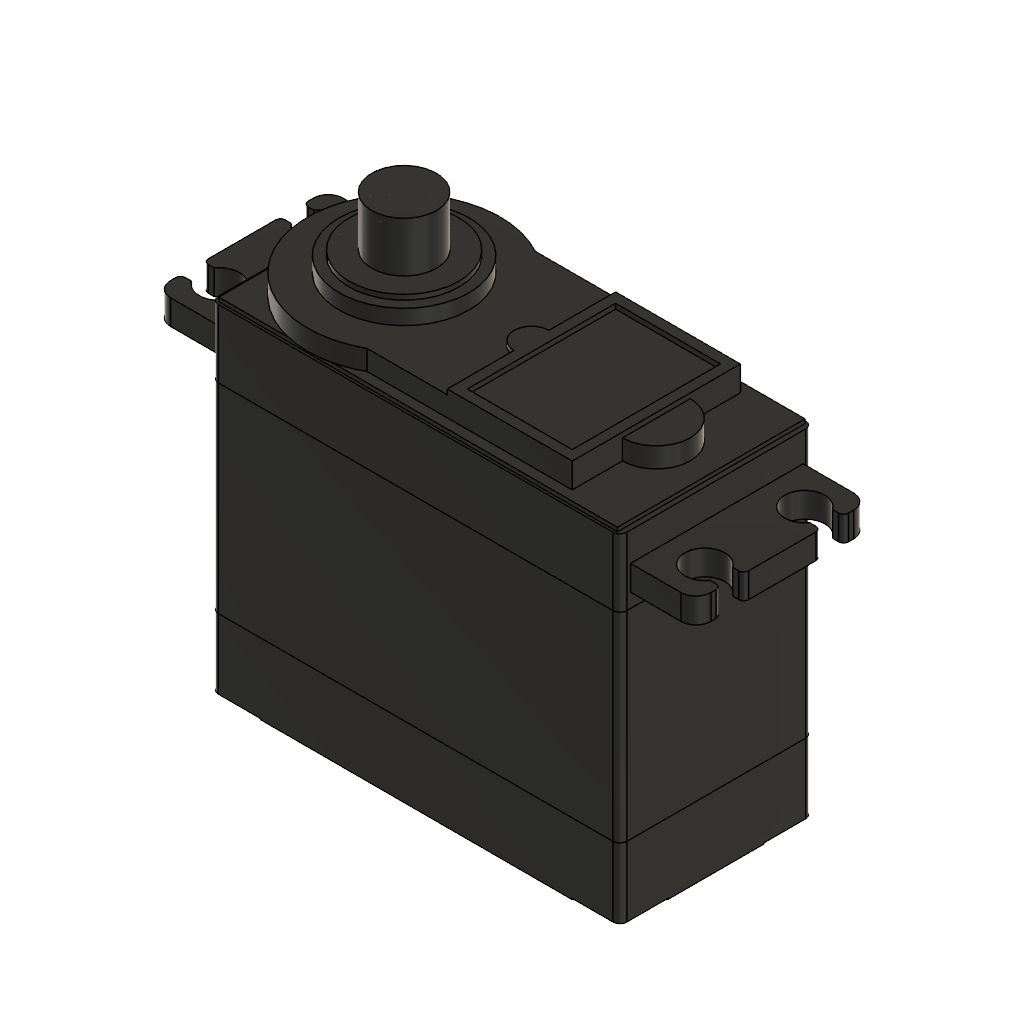
Small_arm_assembly (Autodesk Fusion 360 archive; units mm, degrees)
design "small_arm_servo_black"
part number: 2026-10-12-23-47-02-979
Autodesk Fusion 360 part; units mm, degrees
sketch "Sketch1" plane through (0, 0, 0) normal (0, 1, 0) x (1, 0, 0)
  line L0 (20.45, -10) -> (-20.45, -10)
  line L1 (-20.45, -10) -> (-20.45, 10)
  line L2 (-20.45, 10) -> (20.45, 10)
  line L3 (20.45, 10) -> (20.45, -10)
  line L4 (20.45, -10) -> (-20.45, 10) construction
  line L5 (-20.45, -10) -> (20.45, 10) construction
  dimension "d1" = 20
  dimension "d2" = 40.9
  constraint horizontal L0
  constraint perpendicular L0 L1
  constraint parallel L0 L2
  constraint parallel L1 L3
  constraint coincident L4 origin
  constraint coincident L5 origin
  measures "d1" distance of L0.start L2.end
  measures "d2" distance of L1.end L2.end
extrude "Extrude1" add sketch "Sketch1" along normal blind 19.3 contours L0 L1 L2 L3 picked at (-6.816667, -3.333333) makes body 1
sketch "Sketch2" plane through (0, 0, 10) normal (0, 0, 1) x (-1, 0, 0)
  line L0 (20.45, 0) -> (-20.45, 0)
  line L1 (-20.45, 0) -> (-20.45, -19.3)
  line L2 (-20.45, -19.3) -> (20.45, -19.3)
  line L3 (20.45, -19.3) -> (20.45, 0)
  line L4 (20.45, 0) -> (-20.45, 0)
  line L5 (-20.45, 0) -> (-20.45, -19.3)
  line L6 (-20.45, -19.3) -> (20.45, -19.3)
  line L7 (20.45, -19.3) -> (20.45, 0)
  dimension "d5" = 0
  measures "d5" distance of L2
extrude "Extrude2" add sketch "Sketch2" along normal blind 6.8 separate body contours L0 L1 L2 L3 L4 L5 L6 L7 picked at (-6.816667, -6.433333) makes body 2
sketch "Sketch3" plane through (0, 0, -10) normal (0, 0, -1) x (1, 0, 0)
  line L0 (20.45, 0) -> (-20.45, 0)
  line L1 (-20.45, 0) -> (-20.45, -19.3)
  line L2 (-20.45, -19.3) -> (20.45, -19.3)
  line L3 (20.45, -19.3) -> (20.45, 0)
  line L4 (-20.45, -19.3) -> (20.45, -19.3)
  line L5 (20.45, -19.3) -> (20.45, 0)
  line L6 (20.45, 0) -> (-20.45, 0)
  line L7 (-20.45, 0) -> (-20.45, -19.3)
  dimension "d8" = 0
  measures "d8" distance of L0
extrude "Extrude3" add sketch "Sketch3" along normal blind 8.5 separate body contours L0 L1 L2 L3 L4 L5 L6 L7 picked at (-6.816667, -6.433333) makes body 3
chamfer "Chamfer1" distance 2 angle 35 1 faces at (-6.816667, 6.433333, -18.5) tangent chain off on bodies 3
sketch "Sketch4" plane through (0, 0, -18.5) normal (0, 0, -1) x (1, 0, 0)
  line L0 (18.45, -17.3) -> (18.45, -2)
  line L1 (18.45, -2) -> (-18.45, -2)
  line L2 (-18.45, -2) -> (-18.45, -17.3)
  line L3 (-18.45, -17.3) -> (18.45, -17.3)
  line L4 (-20.450001, 0) -> (-15.570001, 0)
  line L5 (-15.570001, 0) -> (-15.570001, -2.88)
  line L6 (-17.570001, -4.88) -> (-20.450001, -4.88)
  line L7 (-20.450001, -4.88) -> (-20.450001, 0)
  arc A0 (-17.570001, -4.88) -> (-15.570001, -2.88) centre (-17.570001, -2.88) ccw
  line L8 (0, 0) -> (0, -19.328376) construction
  line L9 (20.450001, 0) -> (15.570001, 0)
  line L10 (20.450001, -4.88) -> (20.450001, 0)
  line L11 (17.570001, -4.88) -> (20.450001, -4.88)
  line L12 (15.570001, 0) -> (15.570001, -2.88)
  arc A1 (15.570001, -2.88) -> (17.570001, -4.88) centre (17.570001, -2.88) ccw
  line L13 (18.45, -9.65) -> (0, -9.664188) construction
  line L14 (-20.435113, -19.359816) -> (-15.555119, -19.352311)
  line L15 (-20.442619, -14.479822) -> (-20.435113, -19.359816)
  line L16 (-17.562622, -14.475392) -> (-20.442619, -14.479822)
  line L17 (-15.555119, -19.352311) -> (-15.559549, -16.472314)
  arc A2 (-15.559549, -16.472314) -> (-17.562622, -14.475392) centre (-17.559546, -16.47539) ccw
  line L18 (20.46484, -19.296913) -> (15.584846, -19.304418)
  line L19 (15.584846, -19.304418) -> (15.580416, -16.424421)
  arc A3 (17.577338, -14.421348) -> (15.580416, -16.424421) centre (17.580414, -16.421345) ccw
  line L20 (17.577338, -14.421348) -> (20.457335, -14.416918)
  line L21 (20.457335, -14.416918) -> (20.46484, -19.296913)
  dimension "d13" = 4.88
  dimension "d14" = 4.88
  dimension "d15" = 2
  constraint horizontal L4
  constraint vertical L5
  constraint horizontal L6
  constraint vertical L7
  constraint tangent L5 A0
  constraint tangent L6 A0
  constraint coincident L8.start origin
  constraint vertical L8
  constraint symmetric A0 L8 A1
  constraint midpoint L0 L13.start
  constraint symmetric A0 L13 A2
  constraint symmetric A1 L13 A3
  measures "d15" radius of A0
extrude "Extrude4" cut sketch "Sketch4" against normal blind 1.5 contours L0 L3 L19 A3 L20 | L0 L3 L18 L19 L20 L21 | L0 L1 L11 L12 A1 | L0 L1 L9 L10 L11 L12 | L2 L3 L14 L15 L16 L17 | L2 L3 L16 L17 A2 | L1 L2 L5 L6 A0 | L1 L2 L4 L5 L6 L7 picked at (16.537393, -17.00814) picked at (19.790725, -17.00461) picked at (16.530001, -2.293333) picked at (19.783334, -2.293333) picked at (-18.146744, -18.670709) picked at (-18.154207, -15.417383) picked at (-16.530001, -2.293333) picked at (-19.783334, -2.293333) bodies 3
sketch "Sketch5" plane through (0, 0, 16.8) normal (0, 0, 1) x (-1, 0, 0)
  line L0 (20.45, -19.3) -> (20.45, 0)
  line L1 (20.45, 0) -> (-20.45, 0)
  line L2 (-20.45, 0) -> (-20.45, -19.3)
  line L3 (-20.45, -19.3) -> (20.45, -19.3)
  line L4 (0, -19.3) -> (0, 0)
  line L5 (-19.95, -19.05) -> (19.95, -19.05)
  line L6 (19.95, -19.05) -> (19.95, -0.25)
  line L7 (19.95, -0.25) -> (-19.95, -0.25)
  line L8 (-19.95, -0.25) -> (-19.95, -19.05)
  line L9 (-19.95, -19.05) -> (19.95, -0.25) construction
  line L10 (19.95, -19.05) -> (-19.95, -0.25) construction
  point P0 (0, -9.65)
  dimension "d18" = 0.25
  dimension "d19" = 0.5
  constraint midpoint L3 L4.start
  constraint coincident L4.end origin
  constraint horizontal L5
  constraint perpendicular L5 L6
  constraint parallel L5 L7
  constraint parallel L6 L8
  constraint coincident L9 P0
  constraint coincident L10 P0
  constraint midpoint L4 P0
  measures "d18" distance of L3 L5
  measures "d19" distance of L2 L8
extrude "Extrude5" add sketch "Sketch5" along normal blind 0.4 contours L4 L5 L7 L8 | L4 L5 L6 L7 picked at (-13.3, -12.783333) picked at (13.3, -12.783333) bodies 2
sketch "Sketch6" plane through (0, 0, 17.2) normal (0, 0, 1) x (-1, 0, 0)
  line L0 (-19.95, -0.25) -> (-19.95, -19.05)
  line L1 (-19.95, -19.05) -> (19.95, -19.05)
  line L2 (19.95, -19.05) -> (19.95, -0.25)
  line L3 (19.95, -0.25) -> (-19.95, -0.25)
  line L4 (19.95, -9.65) -> (-20.844849, -9.65)
  line L5 (-20.45, -19.3) -> (20.45, -19.3)
  line L6 (20.45, -19.3) -> (20.45, 0)
  line L7 (6.09, -20) -> (6.09, 5)
  arc A0 (6.09, -18.072494) -> (6.09, -1.227506) centre (10.8, -9.65) ccw
  line L8 (6.09, -18.072494) -> (-14.45, -18.072494)
  line L9 (-20.45, 0) -> (-20.45, -19.3)
  line L10 (-14.45, -18.072494) -> (-14.45, -13.044849)
  arc A1 (-17.844849, -9.65) -> (-14.45, -13.044849) centre (-14.45, -9.65) ccw
  line L11 (6.09, -1.227506) -> (-14.45, -1.227506)
  line L12 (-14.45, -1.227506) -> (-14.45, -6.255151)
  arc A2 (-14.45, -6.255151) -> (-17.844849, -9.65) centre (-14.45, -9.65) ccw
  dimension "d22" = 14.36
  dimension "d25" = 6
  dimension "d26" = 3
  constraint midpoint L2 L4.start
  constraint perpendicular L0 L4
  constraint coincident L4 A0.centre
  constraint tangent L5 A0
  constraint tangent L6 A0
  constraint perpendicular L1 L7
  constraint horizontal L8
  constraint coincident L4 A1.centre
  constraint perpendicular L10 A1
  constraint symmetric L4 A1 A2
  measures "d22" distance of L6 L7.end
extrude "Extrude6" add sketch "Sketch6" along normal blind 2 contours L4 L7 L11 L12 A2 | L4 L7 L8 L10 A1 | L3 A0 | L2 L3 L4 L7 A0 | L1 L2 L4 L7 A0 | L1 A0 | L2 A0 picked at (-0.756667, -5.710886) picked at (-0.756667, -13.589114) picked at (10.8, -0.166667) picked at (14.908099, -7.795265) picked at (14.908099, -11.504735) picked at (11.287307, -19.096207) picked at (20.264671, -9.304002) bodies 2
sketch "Sketch7" plane through (0, 0, 19.2) normal (0, 0, 1) x (-1, 0, 0)
  arc A0 (6.09, -18.072494) -> (6.09, -1.227506) centre (10.8, -9.65) ccw
  line L0 (6.09, -1.227506) -> (-14.45, -1.227506)
  line L1 (-14.45, -1.227506) -> (-14.45, -6.255151)
  arc A1 (-14.45, -6.255151) -> (-14.45, -13.044849) centre (-14.45, -9.65) ccw
  line L2 (-14.45, -13.044849) -> (-14.45, -18.072494)
  line L3 (-14.45, -18.072494) -> (6.09, -18.072494)
  circle A2 centre (10.8, -9.65) radius 6.5
  dimension "d29" = 13
  constraint concentric A0 A2
  measures "d29" diameter of A2
extrude "Extrude7" add sketch "Sketch7" along normal blind 1.5 contours A2 picked at (9.021353, -11.740864) bodies 2
sketch "Sketch8" plane through (0, 0, 20.7) normal (0, 0, 1) x (-1, 0, 0)
  circle A0 centre (10.8, -9.65) radius 6.5
  circle A1 centre (10.8, -9.65) radius 5.5
  dimension "d32" = 11
  constraint concentric A0 A1
  measures "d32" diameter of A1
extrude "Extrude8" add sketch "Sketch8" along normal blind 0.5 contours A1 picked at (14.20366, -10.985838) bodies 2
sketch "Sketch9" plane through (0, 0, 21.2) normal (0, 0, 1) x (-1, 0, 0)
  circle A0 centre (10.8, -9.65) radius 5.5
  circle A1 centre (10.8, -9.65) radius 3.25
  dimension "d35" = 6.5
  constraint concentric A0 A1
  measures "d35" diameter of A1
extrude "Extrude9" add sketch "Sketch9" along normal blind 5 contours A1 picked at (11.651589, -11.26871) bodies 2
sketch "Sketch10" plane through (0, 0, 19.2) normal (0, 0, 1) x (-1, 0, 0)
  circle A0 centre (10.8, -9.65) radius 6.5
  arc A1 (6.09, -18.072494) -> (6.09, -1.227506) centre (10.8, -9.65) ccw
  line L0 (6.09, -1.227506) -> (-14.45, -1.227506)
  line L1 (-14.45, -1.227506) -> (-14.45, -6.255151)
  arc A2 (-14.45, -6.255151) -> (-14.45, -13.044849) centre (-14.45, -9.65) ccw
  line L2 (-14.45, -13.044849) -> (-14.45, -18.072494)
  line L3 (-14.45, -18.072494) -> (6.09, -18.072494)
  line L4 (-14.45, -18.072494) -> (-1.95, -18.072494)
  line L5 (-1.95, -1.227506) -> (-14.45, -1.227506)
  line L6 (-14.45, -1.227506) -> (-14.45, -18.072494)
  line L7 (-13.45, -17.072494) -> (-2.95, -17.072494)
  line L8 (-2.95, -17.072494) -> (-2.95, -2.227506)
  line L9 (-2.95, -2.227506) -> (-13.45, -2.227506)
  line L10 (-13.45, -2.227506) -> (-13.45, -17.072494)
  arc A3 (-1.95, -11.4) -> (-1.95, -7.9) centre (-1.95, -9.65) ccw
  line L11 (-1.95, -18.072494) -> (-1.95, -11.4)
  line L12 (-1.95, -7.9) -> (-1.95, -1.227506)
  dimension "d38" = 12.5
  dimension "d40" = 3.5
  dimension "d41" = 1
  dimension "d42" = 1
  dimension "d43" = 1
  dimension "d44" = 1
  constraint horizontal L4
  constraint vertical L11
  constraint horizontal L5
  constraint vertical L6
  constraint collinear L11 L12
  constraint coincident A3.centre L11
  measures "d40" diameter of A3
  measures "d41" distance of L4 L7
  measures "d42" distance of L8 L11
  measures "d43" distance of L5 L9
  measures "d44" distance of L6 L10
extrude "Extrude10" add sketch "Sketch10" along normal blind 0.5 contours L0 L1 L2 L3 L4 L5 L6 A3 L11 L12 picked at (-13.783333, -8.518384) bodies 2
fillet "Fillet1" radius 0.7 4 edges at (20.45, 0, 0) (20.45, 19.3, 0) (-20.45, 0, 0) (-20.45, 19.3, 0) on bodies 1
fillet "Fillet2" radius 0.7 4 edges at (-20.45, 19.3, 13.4) (-20.45, 0, 13.4) (20.45, 0, 13.4) (20.45, 19.3, 13.4) on bodies 2
fillet "Fillet3" radius 0.7 4 edges at (20.45, 0, -13.5) (20.45, 19.3, -13.549792) (-20.45, 0, -13.5) (-20.45, 19.3, -13.549792) on bodies 3
sketch "Sketch11" plane through (0, 0, 17.2) normal (0, 0, 1) x (-1, 0, 0)
  arc A0 (6.09, -18.072494) -> (8.617685, -19.05) centre (10.8, -9.65) ccw
  line L0 (6.09, -18.072494) -> (-14.45, -18.072494)
  line L1 (-14.45, -18.072494) -> (-14.45, -13.044849)
  arc A1 (-14.45, -6.255151) -> (-14.45, -13.044849) centre (-14.45, -9.65) ccw
  line L2 (-14.45, -6.255151) -> (-14.45, -1.227506)
  line L3 (-14.45, -1.227506) -> (6.09, -1.227506)
  arc A2 (8.617685, -0.25) -> (6.09, -1.227506) centre (10.8, -9.65) ccw
  line L4 (8.617685, -0.25) -> (-19.95, -0.25)
  line L5 (-19.95, -0.25) -> (-19.95, -19.05)
  line L6 (-19.95, -19.05) -> (8.617685, -19.05)
  line L7 (-20.5, -18.3) -> (-25.55, -18.3)
  line L8 (-0.197497, -9.659083) -> (-48.000001, -9.659083)
  line L9 (-19.75, -19.3) -> (19.75, -19.3)
  line L10 (0, -19.3) -> (0, 0)
  line L11 (-25.95, -18.3) -> (-25.95, -9.659083)
  arc A3 (-25.95, -15.789348) -> (-25.95, -13.528818) centre (-24.3, -14.659083) ccw
  line L12 (-25.95, -15.789348) -> (-26.55, -15.789348)
  line L13 (-25.95, -13.528818) -> (-26.55, -13.528818)
  line L14 (-27.05, -16.8) -> (-27.05, -16.289348)
  line L15 (-27.05, -13.028818) -> (-27.05, -9.659083)
  arc A4 (-26.55, -15.789348) -> (-27.05, -16.289348) centre (-26.55, -16.289348) ccw
  arc A5 (-27.05, -13.028818) -> (-26.55, -13.528818) centre (-26.55, -13.028818) ccw
  arc A6 (-27.05, -16.8) -> (-25.55, -18.3) centre (-25.55, -16.8) ccw
  line L16 (-25.95, -3.528818) -> (-26.55, -3.528818)
  line L17 (-27.05, -2.518166) -> (-27.05, -3.028818)
  arc A7 (-25.95, -5.789348) -> (-25.95, -3.528818) centre (-24.3, -4.659083) ccw
  arc A8 (-25.55, -1.018166) -> (-27.05, -2.518166) centre (-25.55, -2.518166) ccw
  arc A9 (-27.05, -3.028818) -> (-26.55, -3.528818) centre (-26.55, -3.028818) ccw
  arc A10 (-26.55, -5.789348) -> (-27.05, -6.289348) centre (-26.55, -6.289348) ccw
  line L18 (-20.5, -1.018166) -> (-25.55, -1.018166)
  line L19 (-25.95, -5.789348) -> (-26.55, -5.789348)
  line L20 (-27.05, -6.289348) -> (-27.05, -9.659083)
  line L21 (-20.5, -18.3) -> (-20.5, -1.018166)
  line L22 (25.95, -15.789348) -> (26.55, -15.789348)
  line L23 (25.95, -18.3) -> (25.95, -9.659083)
  line L24 (27.05, -13.028818) -> (27.05, -9.659083)
  line L25 (20.5, -18.3) -> (25.55, -18.3)
  line L26 (25.95, -3.528818) -> (26.55, -3.528818)
  arc A11 (27.05, -16.289348) -> (26.55, -15.789348) centre (26.55, -16.289348) ccw
  arc A12 (27.05, -6.289348) -> (26.55, -5.789348) centre (26.55, -6.289348) ccw
  line L27 (20.5, -18.3) -> (20.5, -1.018166)
  arc A13 (27.05, -2.518166) -> (25.55, -1.018166) centre (25.55, -2.518166) ccw
  arc A14 (25.95, -3.528818) -> (25.95, -5.789348) centre (24.3, -4.659083) ccw
  line L28 (25.95, -5.789348) -> (26.55, -5.789348)
  arc A15 (25.95, -13.528818) -> (25.95, -15.789348) centre (24.3, -14.659083) ccw
  line L29 (27.05, -6.289348) -> (27.05, -9.659083)
  arc A16 (26.55, -3.528818) -> (27.05, -3.028818) centre (26.55, -3.028818) ccw
  line L30 (27.05, -16.8) -> (27.05, -16.289348)
  line L31 (20.5, -1.018166) -> (25.55, -1.018166)
  line L32 (25.95, -13.528818) -> (26.55, -13.528818)
  arc A17 (25.55, -18.3) -> (27.05, -16.8) centre (25.55, -16.8) ccw
  line L33 (27.05, -2.518166) -> (27.05, -3.028818)
  arc A18 (26.55, -13.528818) -> (27.05, -13.028818) centre (26.55, -13.028818) ccw
  line L34 (0.197497, -9.659083) -> (48.000001, -9.659083)
  point P0 (-27.05, -18.3)
  point P1 (-25.95, -1.018166)
  point P2 (-19.95, -0.268166)
  point P3 (-19.75, -0.018166)
  point P4 (-27.05, -1.018166)
  point P5 (19.95, -19.05)
  point P6 (27.05, -1.018166)
  point P7 (19.95, -0.25)
  point P8 (27.05, -18.3)
  point P9 (25.95, -1.018166)
  point P10 (19.95, -0.268166)
  dimension "d53" = 6.55
  dimension "d55" = 4
  dimension "d56" = 5
  dimension "d57" = 1
  dimension "d58" = 1.1
  dimension "d59" = 24.3
  dimension "d60" = 0.5
  dimension "d61" = 1.5
  constraint horizontal L7
  constraint parallel L6 L8
  constraint perpendicular L8 L15
  constraint midpoint L9 L10.start
  constraint coincident L10.end origin
  constraint coincident L7 L11.start
  constraint perpendicular L8 L11
  constraint perpendicular L12 L14
  constraint perpendicular L13 L15
  constraint collinear L14 L15
  constraint tangent L12 A4
  constraint tangent L14 A4
  constraint tangent L13 A5
  constraint tangent L15 A5
  constraint equal A4 A5
  constraint coincident P0 L7
  constraint coincident P0 L14
  constraint tangent L7 A6
  constraint tangent L14 A6
  constraint symmetric L8 A3 A7
  constraint symmetric L8 A4 A9
  constraint symmetric L8 A5 A10
  constraint symmetric L8 A6 A8
  constraint symmetric L4.end L10 P7
  constraint symmetric L5.end L10 P5
  constraint symmetric L7.start L10 L25.start
  constraint symmetric P0 L10 P8
  constraint symmetric L10 L11.start L23.start
  constraint symmetric L10 A3 A15
  constraint symmetric L10 A4 A11
  constraint symmetric L10 A5 A18
  constraint symmetric L10 L7.end L25.end
  constraint symmetric L10 L14.start L30.start
  constraint symmetric L10 A6 A17
  constraint symmetric L10 A7 A14
  constraint symmetric L10 A8 A13
  constraint symmetric L10 A9 A16
  constraint symmetric L10 A10 A12
  measures "d53" distance of L7.start P0
  measures "d55" diameter of A3
  measures "d57" distance of P0 L9
  measures "d58" distance of P0 L11.start
  measures "d60" radius of A4
  measures "d61" radius of A6
extrude "Extrude11" add sketch "Sketch11" along normal blind 2.5 from surface at -5.74 separate body contours L7 L8 L11 A3 A6 L21 | L8 L16 L17 A7 A8 A9 A10 L18 L19 L20 L21 | L11 L12 L14 A4 A6 | L8 L11 L13 L15 A5 | L22 L23 A11 L30 A17 | L23 L25 L27 A15 A17 L34 | L23 L24 L32 A18 L34 | L26 A12 L27 A13 A14 L28 L29 A16 L31 L33 L34 picked at (-23.434231, -10.675971) picked at (-23.434231, -8.642196) picked at (-26.516667, -16.126232) picked at (-26.316667, -12.07224) picked at (26.516667, -16.126232) picked at (23.434231, -10.675971) picked at (26.316667, -12.07224) picked at (23.434231, -8.642196) makes body 4 at (-21.129568, 11.129411, 11.46) makes body 5 at (21.129568, 11.129411, 11.46)

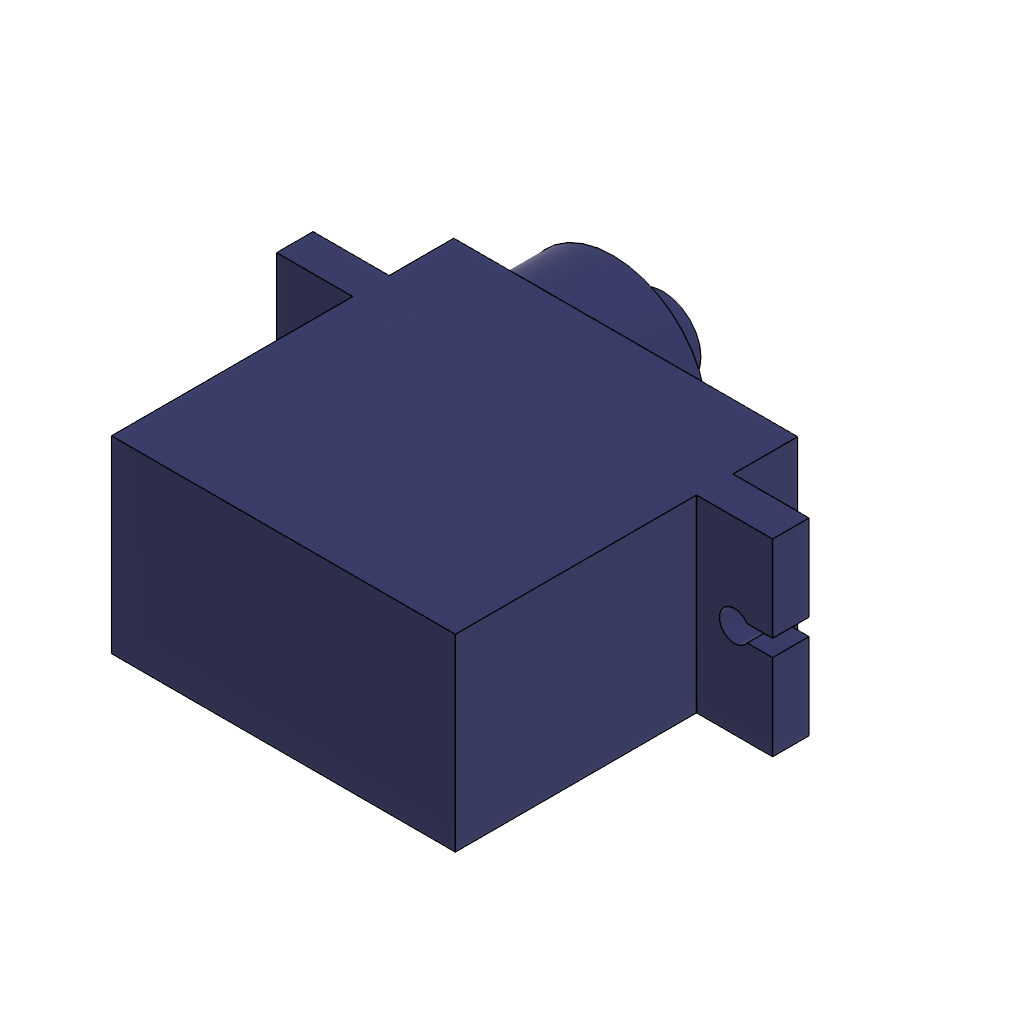
design "gripper_servo"
part number: 2026-10-08-00-42-58-368
Autodesk Fusion 360 part; units mm, degrees
sketch "Sketch6" plane through (0, 0, 0) normal (0, 1, 0) x (1, 0, 0)
  line L0 (11.3, -6.2) -> (-11.3, -6.2)
  line L1 (-11.3, -6.2) -> (-11.3, 6.2)
  line L2 (-11.3, 6.2) -> (11.3, 6.2)
  line L3 (11.3, 6.2) -> (11.3, -6.2)
  line L4 (11.3, -6.2) -> (-11.3, 6.2) construction
  line L5 (-11.3, -6.2) -> (11.3, 6.2) construction
  dimension "d23" = 22.6
  dimension "d24" = 12.4
  constraint horizontal L0
  constraint perpendicular L0 L1
  constraint parallel L0 L2
  constraint parallel L1 L3
  constraint coincident L4 origin
  constraint coincident L5 origin
  measures "d23" distance of L1.end L2.end
  measures "d24" distance of L0.start L2.end
extrude "Extrude6" add sketch "Sketch6" along normal blind 22.5
sketch "Sketch7" plane through (0, 0, 6.2) normal (0, 0, 1) x (-1, 0, 0)
  line L0 (11.3, 0) -> (-11.3, 0)
  line L1 (-11.3, 0) -> (-11.3, -22.5)
  line L2 (-11.3, -22.5) -> (11.3, -22.5)
  line L3 (11.3, -22.5) -> (11.3, 0)
  line L4 (-11.3, -18.25) -> (-16.3, -18.25)
  line L5 (-16.3, -18.25) -> (-16.3, -15.85)
  line L6 (-16.3, -15.85) -> (-11.3, -15.85)
  line L7 (-11.3, -15.85) -> (-11.3, -18.25)
  line L8 (0, -22.5) -> (0, 0)
  line L9 (11.3, -18.25) -> (16.3, -18.25)
  line L10 (16.3, -18.25) -> (16.3, -15.85)
  line L11 (16.3, -15.85) -> (11.3, -15.85)
  line L12 (11.3, -15.85) -> (11.3, -18.25)
  dimension "d27" = 4.25
  dimension "d28" = 2.4
  dimension "d29" = 5
  constraint horizontal L4
  constraint vertical L5
  constraint horizontal L6
  constraint vertical L7
  constraint coincident L1 L4.start
  constraint midpoint L2 L8.start
  constraint coincident L8.end origin
  constraint symmetric L4.start L8 L9.start
  constraint symmetric L4.end L8 L9.end
  constraint symmetric L5.end L8 L10.end
  constraint symmetric L6.end L8 L11.end
  measures "d27" distance of L2 L4
  measures "d28" distance of L4.end L5.end
  measures "d29" distance of L5.end L6.end
extrude "Extrude7" add sketch "Sketch7" against normal up to surface (12.4 mm away) contours L3 L9 L10 L11 L12 | L1 L4 L5 L6 L7
sketch "Sketch8" plane through (0, 18.25, 0) normal (0, 1, 0) x (-1, 0, 0)
  line L0 (-16.3, -6.2) -> (-11.3, -6.2)
  line L1 (-11.3, -6.2) -> (-11.3, 6.2)
  line L2 (-11.3, 6.2) -> (-16.3, 6.2)
  line L3 (-16.3, 6.2) -> (-16.3, -6.2)
  line L4 (-16.3, 0) -> (16.2827, 0)
  line L5 (0, 6.2122) -> (0, -6)
  line L6 (-16.3, 0.55) -> (-14.6352, 0.55)
  line L7 (-14.6352, -0.55) -> (-16.3, -0.55)
  line L8 (-16.3, -0.55) -> (-16.3, 0.55)
  arc A0 (-14.6352, -0.55) -> (-14.6352, 0.55) centre (-13.8, 0) ccw
  arc A1 (14.6352, 0.55) -> (14.6352, -0.55) centre (13.8, 0) ccw
  line L9 (14.6352, -0.55) -> (16.3, -0.55)
  line L10 (16.3, -0.55) -> (16.3, 0.55)
  line L11 (16.3, 0.55) -> (14.6352, 0.55)
  point P0 (16.3, 0)
  dimension "d32" = 2
  dimension "d33" = 2.5
  dimension "d34" = 1.1
  constraint midpoint L3 L4.start
  constraint perpendicular L3 L4
  constraint vertical L5
  constraint coincident L4 A0.centre
  constraint horizontal L6
  constraint horizontal L7
  constraint vertical L8
  constraint coincident L3 L6.start
  constraint symmetric L4.start L5 P0
  constraint symmetric L5 L6.start L10.end
  constraint symmetric L5 L6.end A1.start
  constraint symmetric L5 L7.start A1.end
  constraint symmetric L5 L7.end L9.end
  constraint symmetric L5 A0 A1
  measures "d32" diameter of A0
  measures "d33" distance of L3 A0.centre
  measures "d34" distance of L6.start L7.end
extrude "Extrude8" cut sketch "Sketch8" against normal blind 19 contours L3 L4 L7 L8 A0 | L3 L4 L6 L8 A0 | A1 L9 L10 L11
sketch "Sketch9" plane through (0, 22.5, 0) normal (0, 1, 0) x (-1, 0, 0)
  line L0 (-11.3, -6.2) -> (11.3, -6.2)
  line L1 (11.3, -6.2) -> (11.3, 6.2)
  line L2 (11.3, 6.2) -> (-11.3, 6.2)
  line L3 (-11.3, 6.2) -> (-11.3, -6.2)
  line L4 (11.3, 0) -> (-11.3, 0)
  arc A0 (-1.1514, 1.299) -> (-1.1514, -1.299) centre (-1.1, 0) ccw
  arc A1 (-0.9186, -1.4888) -> (-0.9186, 1.4888) centre (5.1, 0) ccw
  arc A2 (-0.9186, -1.4888) -> (-1.1514, -1.299) centre (-1.1613, -1.5488) ccw
  arc A3 (-1.1514, 1.299) -> (-0.9186, 1.4888) centre (-1.1613, 1.5488) ccw
  dimension "d37" = 12.4
  dimension "d38" = 2.6
  dimension "d39" = 0.25
  constraint midpoint L1 L4.start
  constraint midpoint L3 L4.end
  constraint coincident L4 A1.centre
  constraint tangent L1 A1
  constraint coincident L4 A0.centre
  constraint tangent A1 A2
  constraint tangent A0 A2
  constraint tangent A0 A3
  constraint tangent A1 A3
  constraint equal A2 A3
  measures "d37" diameter of A1
  measures "d38" diameter of A0
  measures "d39" radius of A2
extrude "Extrude9" add sketch "Sketch9" along normal blind 4.25 contours L4 A0 A1 A2 | L4 A0 A1 A3
sketch "Sketch10" plane through (0, 26.75, 0) normal (0, 1, 0) x (-1, 0, 0)
  arc A0 (-0.9186, -1.4888) -> (-0.9186, 1.4888) centre (5.1, 0) ccw
  arc A1 (-1.1514, 1.299) -> (-0.9186, 1.4888) centre (-1.1613, 1.5488) ccw
  arc A2 (-1.1514, 1.299) -> (-1.1514, -1.299) centre (-1.1, 0) ccw
  arc A3 (-0.9186, -1.4888) -> (-1.1514, -1.299) centre (-1.1613, -1.5488) ccw
  circle A4 centre (5.1, 0) radius 2.5
  dimension "d42" = 5
  constraint concentric A0 A4
  measures "d42" diameter of A4
extrude "Extrude10" add sketch "Sketch10" along normal blind 3.3 contours A4

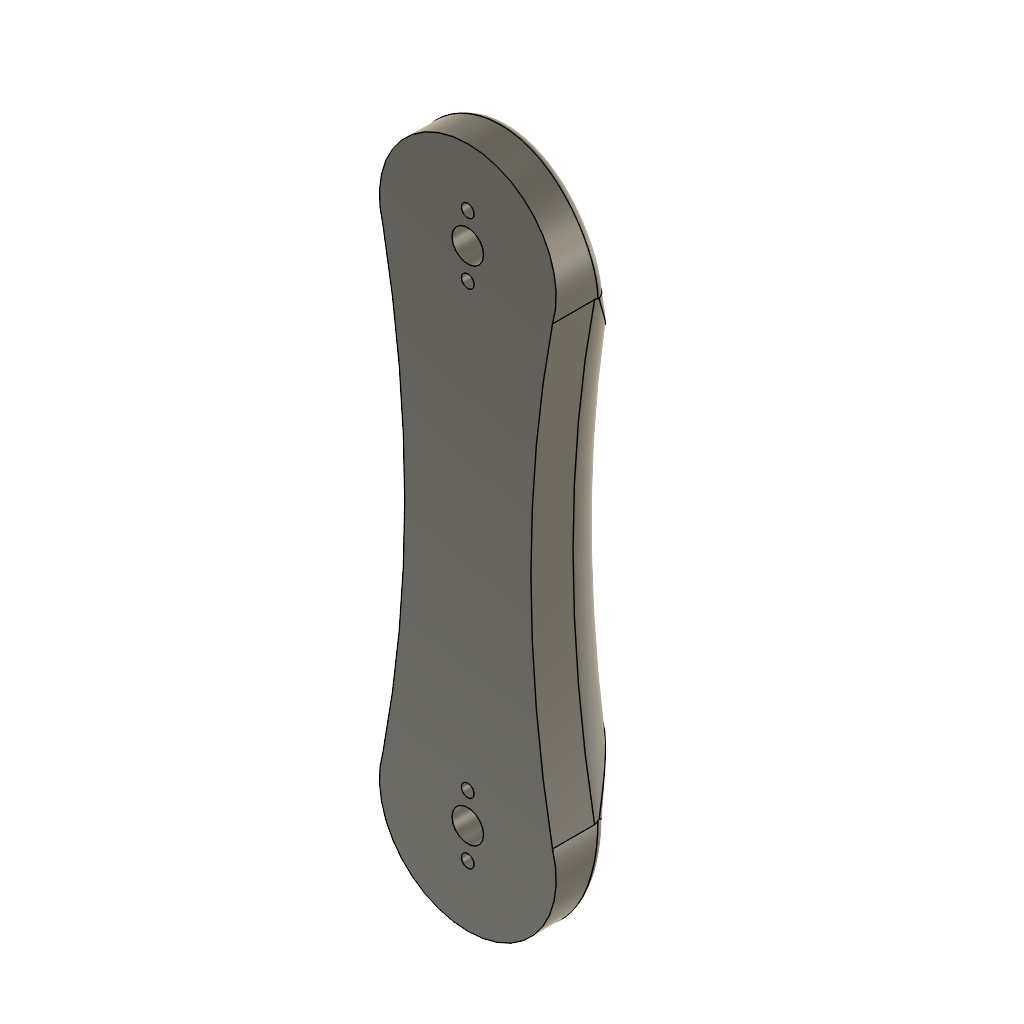
design "small_link1_arm"
part number: 2026-10-10-10-59-52-206
Autodesk Fusion 360 part; units mm, degrees
sketch "Sketch1" plane through (0, 0, 0) normal (0, 1, 0) x (1, 0, 0)
  circle A0 centre (0, -59.6389) radius 21
  circle A1 centre (0, 60.3611) radius 21
  line L0 (0, -59.6389) -> (0, 60.3611) construction
  arc A2 (-20.1246, -53.6389) -> (-20.1246, 54.3611) centre (-302.0589, 0.3611) ccw
  arc A3 (20.1246, 54.3611) -> (20.1246, -53.6389) centre (302.0589, 0.3611) ccw
  point P0 (-15, 0)
  point P1 (15, 0)
  dimension "d1" = 42
  dimension "d2" = 120
  dimension "d3" = 15
  dimension "d4" = 6
  dimension "d5" = 6
  constraint equal A0 A1
  constraint coincident A0.centre L0.start
  constraint coincident A1.centre L0.end
  constraint vertical L0
  constraint symmetric L0 P0 P1
  constraint coincident P0 A2
  constraint coincident A1 A2.end
  constraint coincident A0 A2.start
  constraint symmetric L0 A2.start A3.end
  constraint symmetric L0 A2.end A3.start
  constraint symmetric L0 A2 A3
  measures "d1" diameter of A1
  measures "d2" distance of A0.centre A1.centre
  measures "d3" distance of origin P0
  measures "d4" vertical distance of A0.centre A2.start
  measures "d5" vertical distance of A1.centre A2.end
extrude "Extrude1" add sketch "Sketch1" along normal blind 21
sketch "Sketch2" plane through (0, 0, 0) normal (1, 0, 0) x (0, 1, 0)
  line L0 (21, 80.6415) -> (10, 80.6415)
  line L1 (21, 80.6415) -> (21, 38.6415)
  arc A0 (10, 80.6415) -> (21, 38.6415) centre (69.6102, 73.8132) ccw
  line L2 (-47.5, -0.3687) -> (47.5, -0.3687) construction
  line L3 (0, -54.3611) -> (21, -54.3611) construction
  line L4 (0, -81.5797) -> (0, 80.8423) construction
  arc A1 (21, -39.3789) -> (10, -81.3789) centre (69.6102, -74.5506) ccw
  line L5 (21, -81.3789) -> (21, -39.3789)
  line L6 (21, -81.3789) -> (10, -81.3789)
  dimension "d8" = 11
  dimension "d9" = 42
  dimension "d10" = 60
  constraint horizontal L0
  constraint perpendicular L0 L1
  constraint horizontal L2
  constraint vertical L4
  constraint midpoint L2 L4
  constraint symmetric L0.start L2 L5.start
  constraint symmetric L0.end L2 A1.end
  constraint symmetric L1.end L2 A1.start
  constraint symmetric A0 L2 A1
  measures "d8" distance of L0.start L0.end
  measures "d9" distance of L0.start L1.end
  measures "d10" radius of A0
extrude "Extrude2" cut sketch "Sketch2" along normal through all and the other way through all
fillet "Fillet1" radius 11 2 edges at (-14.9998, 21, -0.3688) (14.9998, 21, -0.3688)
sketch "Sketch3" plane through (0, 0, 0) normal (0, 0, 1) x (1, 0, 0)
  circle A0 centre (0, 12) radius 5.75
  line L0 (-6.5626, 21) -> (6.5626, 21)
  dimension "d15" = 11.5
  dimension "d16" = 9
  measures "d15" diameter of A0
  measures "d16" distance of A0.centre L0
extrude "Extrude3" cut sketch "Sketch3" along normal mid plane 125
fillet "Fillet2" radius 2 14 edges at (-12.9517, 19.2339, 41.2202) (0, 21, 38.6415) (12.8489, 19.2914, 41.132) (19.1996, 14.0626, 51.1315) (16.9366, 9.636, 72.0544) (-16.9366, 9.636, 72.0544) (-19.1996, 14.0626, 51.1315) (12.9437, 19.2396, -41.9488) (0, 21, -39.3789) (-12.8413, 19.2967, -41.8611) (-19.1949, 14.0731, -51.8432) (-16.9368, 9.6365, -72.7762) (16.9368, 9.6365, -72.7762) (19.1949, 14.0731, -51.8432)
sketch "Sketch4" plane through (0, 0, 0) normal (0, -1, 0) x (1, 0, 0)
  arc A0 (20.1246, 53.6389) -> (-20.1246, 53.6389) centre (0, 59.6389) ccw
  arc A1 (-20.1246, -54.3611) -> (-20.1246, 53.6389) centre (-302.0589, -0.3611) ccw
  arc A2 (-20.1246, -54.3611) -> (20.1246, -54.3611) centre (0, -60.3611) ccw
  arc A3 (20.1246, 53.6389) -> (20.1246, -54.3611) centre (302.0589, -0.3611) ccw
  arc A4 (17.2078, 54.3575) -> (17.2078, -55.0798) centre (302.0589, -0.3611) ccw
  arc A5 (-17.2078, -55.0798) -> (17.2078, -55.0798) centre (0, -60.3611) ccw
  arc A6 (-17.2078, -55.0798) -> (-17.2078, 54.3575) centre (-302.0589, -0.3611) ccw
  arc A7 (17.2078, 54.3575) -> (-17.2078, 54.3575) centre (0, 59.6389) ccw
  circle A8 centre (0, -60.3611) radius 18
  circle A9 centre (0, 59.6389) radius 18
  dimension "d21" = -3
  constraint concentric A2 A8
  constraint concentric A0 A9
extrude "Extrude4" cut sketch "Sketch4" against normal blind 60 from surface at -6 contours A7 A9 | A5 A8
sketch "Sketch5" plane through (0, 6, 0) normal (0, 1, 0) x (-1, 0, 0)
  circle A0 centre (0, 59.6389) radius 18
  circle A1 centre (0, 59.6389) radius 3.75
  circle A2 centre (0, 52.3889) radius 1.5
  line L0 (0, 59.6389) -> (-51.5271, 59.6389) construction
  circle A3 centre (0, 66.8889) radius 1.5
  line L1 (0, 0) -> (-138.8169, 0) construction
  circle A4 centre (0, -59.6389) radius 3.75
  circle A5 centre (0, -52.3889) radius 1.5
  circle A6 centre (0, -66.8889) radius 1.5
  dimension "d25" = 7.5
  dimension "d26" = 3
  dimension "d27" = 7.25
  constraint concentric A0 A1
  constraint coincident A0.centre A1.centre
  constraint horizontal L0
  constraint symmetric A2 L0 A3
  constraint coincident L1.start origin
  constraint horizontal L1
  constraint symmetric A1 L1 A4
  constraint symmetric A2 L1 A5
  constraint symmetric A3 L1 A6
  measures "d25" diameter of A1
  measures "d26" diameter of A2
  measures "d27" distance of A0.centre A2.centre
extrude "Extrude5" cut sketch "Sketch5" against normal blind 60 contours A1 | A2 | A3 | A4 | A5 | A6

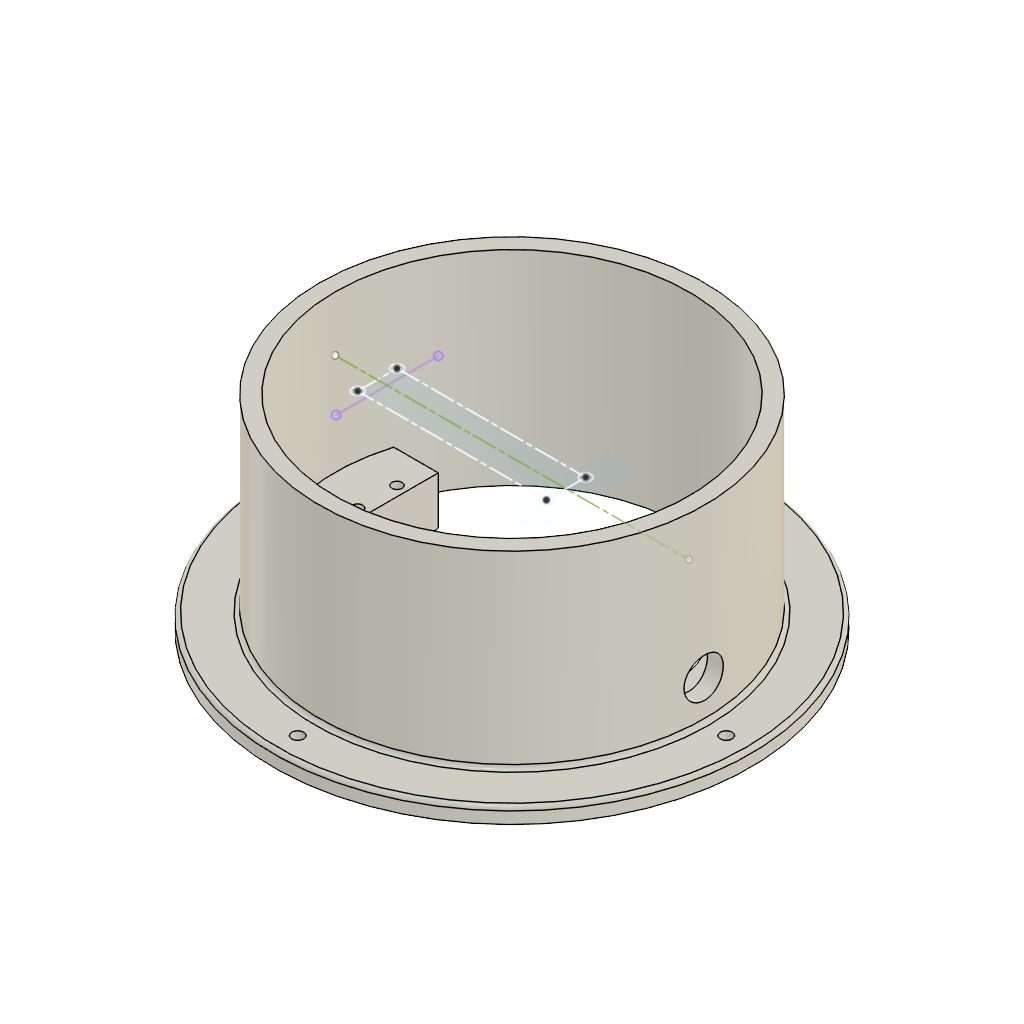
design "small_base_arm"
part number: 2026-10-10-00-16-57-453
Autodesk Fusion 360 part; units mm, degrees
sketch "Sketch1" plane through (0, 0, 0) normal (0, 0, 1) x (1, 0, 0)
  circle A0 centre (0, 0) radius 45
  circle A1 centre (0, 0) radius 60.625
  dimension "d1" = 90
  dimension "d2" = 121.25
  constraint coincident A0.centre A1.centre
  measures "d1" diameter of A0
  measures "d2" diameter of A1
extrude "Extrude1" add sketch "Sketch1" along normal blind 4 makes body 1
sketch "Sketch2" plane through (0, 0, 0) normal (0, 0, 1) x (1, 0, 0)
  circle A0 centre (0, 0) radius 45
  circle A1 centre (0, 0) radius 49
  dimension "d5" = 90
  dimension "d6" = 98
  constraint coincident A0.centre A1.centre
  constraint concentric A0 A1
  measures "d5" diameter of A0
  measures "d6" diameter of A1
extrude "Extrude2" add sketch "Sketch2" along normal blind 52 bodies 1
sketch "Sketch3" plane through (0, 0, 0) normal (0, 1, 0) x (1, 0, 0)
  line L0 (-46.75, -34) -> (-31.75, -34)
  line L1 (-31.75, -34) -> (-31.75, -26)
  line L2 (-31.75, -26) -> (-46.75, -26)
  line L3 (-46.75, -26) -> (-46.75, -34)
  line L4 (11.25, -38) -> (19.25, -38)
  line L5 (19.25, -38) -> (19.25, 0)
  line L6 (19.25, 0) -> (11.25, 0)
  line L7 (11.25, 0) -> (11.25, -38)
  line L8 (-49, -52) -> (49, -52)
  line L9 (-60.625, 0) -> (60.625, 0)
  dimension "d9" = 15
  dimension "d10" = 8
  dimension "d11" = 18
  dimension "d12" = 43
  dimension "d13" = 38
  dimension "d14" = 8
  dimension "d15" = 11.25
  constraint horizontal L0
  constraint vertical L1
  constraint horizontal L2
  constraint vertical L3
  constraint horizontal L4
  constraint vertical L5
  constraint horizontal L6
  constraint vertical L7
  measures "d9" distance of L0.start L0.end
  measures "d10" distance of L0.start L2.end
  measures "d11" distance of L0 L8
  measures "d12" distance of L1 L7
  measures "d13" distance of L4.end L9
  measures "d14" distance of L5.end L6.end
  measures "d15" distance of origin L6.end
extrude "Extrude3" add sketch "Sketch3" along normal mid plane 26 contours L0 L1 L2 L3 bodies 1
extrude "Extrude4" add sketch "Sketch3" along normal mid plane 26 separate body contours L4 L5 L6 L7 L9 makes body 2
sketch "Sketch4" plane through (11.25, 0, 0) normal (-1, 0, 0) x (0, -1, 0)
  line L0 (13, 38) -> (-13, 38)
  line L1 (-13, 38) -> (-13, 0)
  line L2 (-13, 0) -> (13, 0)
  line L3 (13, 0) -> (13, 38)
  line L4 (0, 52) -> (0, 0)
  line L5 (5, 5) -> (-5, 5)
  line L6 (-5, 5) -> (-5, 29)
  line L7 (-5, 29) -> (5, 29)
  line L8 (5, 29) -> (5, 5)
  line L9 (5, 5) -> (-5, 29) construction
  line L10 (-5, 5) -> (5, 29) construction
  point P0 (0, 17)
  dimension "d20" = 10
  dimension "d21" = 24
  dimension "d22" = 5
  constraint coincident L4.end origin
  constraint perpendicular L2 L4
  constraint horizontal L5
  constraint perpendicular L5 L6
  constraint parallel L5 L7
  constraint parallel L6 L8
  constraint coincident L9 P0
  constraint coincident L10 P0
  constraint coincident L4 P0
  measures "d20" distance of L6.end L7.end
  measures "d21" distance of L5.start L7.end
  measures "d22" distance of L2 L5.start
extrude "Extrude5" cut sketch "Sketch4" against normal blind 15 contours L4 L5 L7 L8 | L4 L5 L6 L7 bodies 2
sketch "Sketch5" plane through (11.25, 0, 0) normal (-1, 0, 0) x (0, -1, 0)
  line L0 (-5, 5) -> (-5, 29)
  line L1 (-5, 29) -> (5, 29)
  line L2 (5, 29) -> (5, 5)
  line L3 (5, 5) -> (-5, 5)
  line L4 (13, 38) -> (-13, 38)
  line L5 (-13, 38) -> (-13, 0)
  line L6 (-13, 0) -> (13, 0)
  line L7 (13, 0) -> (13, 38)
  line L8 (0, 52.2294) -> (0, 0)
  circle A0 centre (0, 14) radius 5
  line L9 (60.625, 0) -> (-60.625, 0)
  dimension "d25" = 14
  dimension "d26" = 10
  constraint coincident L8.end origin
  constraint perpendicular L6 L8
  constraint coincident L8 A0.centre
  measures "d25" distance of A0.centre L9
  measures "d26" diameter of A0
extrude "Extrude6" cut sketch "Sketch5" against normal blind 75 contours L8 A0 | L8 A0 bodies 1
sketch "Sketch6" plane through (0, 0, 38) normal (0, 0, 1) x (-1, 0, 0)
  line L0 (-19.25, 13) -> (-19.25, -13)
  line L1 (-19.25, -13) -> (-11.25, -13)
  line L2 (-11.25, -13) -> (-11.25, 13)
  line L3 (-11.25, 13) -> (-19.25, 13)
  line L4 (45, 0) -> (-45, 0)
  line L5 (34.25, -5) -> (-13.75, -5)
  line L6 (-13.75, -5) -> (-13.75, 5)
  line L7 (-13.75, 5) -> (34.25, 5)
  line L8 (34.25, 5) -> (34.25, -5)
  line L9 (31.75, 13) -> (31.75, -13)
  circle A0 centre (34.25, -5) radius 1.3
  circle A1 centre (34.25, 5) radius 1.3
  circle A2 centre (-13.75, -5) radius 1.3
  circle A3 centre (-13.75, 5) radius 1.3
  dimension "d29" = 2.5
  dimension "d30" = 2.5
  dimension "d32" = 10
  dimension "d33" = 2.6
  dimension "d34" = 5
  dimension "d35" = 2.6
  constraint horizontal L4
  constraint horizontal L5
  constraint vertical L6
  constraint horizontal L7
  constraint vertical L8
  constraint coincident L5.start L8.end
  constraint coincident L7.end L8.start
  constraint coincident L5.end L6.start
  constraint coincident L6.end L7.start
  constraint equal A1 A2
  constraint equal A1 A3
  measures "d29" distance of L5.start L9
  measures "d30" distance of L2 L5.end
  measures "d33" diameter of A0
  measures "d34" vertical distance of L4.start L5.start
  measures "d35" diameter of A1
extrude "Extrude7" cut sketch "Sketch6" against normal blind 7.2 contours L5 L6 A2 | L5 L6 A2 | L6 L7 A3 | L6 L7 A3 | L7 L8 A1 | L7 L8 A1 | L5 L8 A0 | L5 L8 A0 bodies 1 2
sketch "Sketch7" plane through (0, 0, 0) normal (0, 0, -1) x (1, 0, 0)
  circle A0 centre (0, 0) radius 45
  circle A1 centre (0, 0) radius 60.625
  line L0 (11.25, 13) -> (25.2498, 37.2484)
  line L1 (19, 0) -> (58.1801, 0)
  line L2 (11.25, -13) -> (25.2498, -37.2484)
  arc A2 (25.2498, -37.2484) -> (25.2498, 37.2484) centre (0, 0) ccw
  line L3 (11.25, 13) -> (11.25, -13)
  line L4 (24.25, 19.5167) -> (27.3618, 24.9065)
  arc A3 (27.3618, -24.9065) -> (27.3618, 24.9065) centre (0, 0) ccw
  line L5 (24.25, -19.5167) -> (27.3618, -24.9065)
  line L6 (19.25, 10.8564) -> (19.25, -10.8564)
  line L7 (24.25, -19.5167) -> (24.25, 19.5167)
  dimension "d38" = 60
  dimension "d41" = 5
  dimension "d42" = 8
  dimension "d43" = 8
  dimension "d44" = 8
  constraint coincident A0 L0.end
  constraint horizontal L1
  constraint symmetric L0.start L1 L2.start
  constraint symmetric L0.end L1 L2.end
  constraint concentric A0 A2
  constraint vertical L7
  constraint concentric A2 A3
  measures "d38" angle of L0 L1
  measures "d41" distance of L6 L7
  measures "d42" distance of L0 L4
  measures "d43" distance of L2 L5
  measures "d44" distance of L3 L6
extrude "Extrude8" add sketch "Sketch7" against normal blind 4 contours A0 L0 L2 A2 L3 bodies 1 2
sketch "Sketch8" plane through (0, 0, 0) normal (0, 0, -1) x (1, 0, 0)
  arc A0 (27.3618, -24.9065) -> (27.3618, 24.9065) centre (0, 0) ccw
  line L0 (27.3618, -24.9065) -> (24.25, -19.5167)
  line L1 (24.25, -19.5167) -> (24.25, 19.5167)
  line L2 (24.25, 19.5167) -> (27.3618, 24.9065)
  arc A1 (25.2498, 37.2484) -> (25.2498, -37.2484) centre (0, 0) ccw
  line L3 (25.2498, 37.2484) -> (11.25, 13)
  line L4 (11.25, 13) -> (11.25, -13)
  line L5 (11.25, -13) -> (25.2498, -37.2484)
  circle A2 centre (0, 0) radius 60.625
  circle A3 centre (0, 0) radius 54.5 construction
  circle A4 centre (0, -54.5) radius 1.5
  circle A5 centre (54.5, 0) radius 1.5
  circle A6 centre (0, 54.5) radius 1.5
  circle A7 centre (-54.5, 0) radius 1.5
  dimension "d47" = 109
  dimension "d52" = 3
  dimension "d54" = 360
  constraint coincident A0.centre A1.centre
  constraint coincident A3 A4.centre
  measures "d47" diameter of A3
  measures "d52" diameter of A4
extrude "Extrude9" cut sketch "Sketch8" against normal blind 5 contours A4 | A5 | A6 | A7 bodies 1
fillet "Fillet1" radius 1 2 edges at (-45.684, 17.7192, 4) (-56.5223, -21.9229, 4) on bodies 1
move_face "OffsetFaces1" offset -33 1 faces at (14.8464, 10.7558, 38) on bodies 1
delete_face "DeleteFace1" 1 faces at (12.4565, 5.1294, 21.6) on bodies 1
delete_face "DeleteFace2" 1 faces at (12.4565, -5.1294, 21.6) on bodies 1
extrude "Extrude10" cut sketch "Sketch6" against normal blind 36 contours L5 L6 A2 | L5 L6 A2 | L6 L7 A3 | L6 L7 A3 bodies 1
move_face "OffsetFaces2" offset 26 1 faces at (-36.1667, 0, 26) on bodies 1
move_face "OffsetFaces3" offset -28 1 faces at (-38.4686, 0, 34) on bodies 1
move_face "OffsetFaces4" offset -1 1 faces at (-38.4686, 0, 6) on bodies 1
delete_face "DeleteFace3" 1 faces at (-34.2176, 3.7004, 13.6) on bodies 1
delete_face "DeleteFace4" 1 faces at (-34.2176, -6.2996, 13.6) on bodies 1
extrude "Extrude11" cut sketch "Sketch6" against normal blind 35 contours L7 L8 A1 | L7 L8 A1 | L5 L8 A0 | L5 L8 A0 bodies 1
move_face "OffsetFaces5" offset 7.24 1 faces at (-38.4686, 0, 5) on bodies 1
move_face "OffsetFaces6" offset 7.24 1 faces at (14.8464, 10.7558, 5) on bodies 1
